MOD-GRID Pen Clip 9.84 (Autodesk Fusion 360 design; units mm, degrees)
part number: 2026-10-21-09-21-54-398
Autodesk Fusion 360 part; units mm, degrees
sketch "Clip A body" plane through (0, 0, 0) normal (1, 0, 0) x (0, 0, -1)
  line L0 (0, -11) -> (-11.0844, -11)
  line L1 (-11.0844, -11) -> (-11.0844, 11)
  line L2 (-11.0844, 11) -> (0, 11)
  line L3 (0, 11) -> (0, -11)
extrude "Extrude193" add sketch "Clip A body" along normal blind 7 and the other way blind 7 makes body 1
fillet "Fillet5" radius 2 4 edges at (0, 11, 0) (0, -11, 0) (0, -11, 11.0844) (0, 11, 11.0844) on bodies 1
sketch "Clip A bore" plane through (0, 0, 0) normal (1, 0, 0) x (0, 0, -1)
  circle A0 centre (-7.52, 0) radius 5.02
extrude "Extrude194" cut sketch "Clip A bore" along normal blind 14 and the other way blind 14 bodies 1
sketch "Clip A opening" plane through (0, 0, 0) normal (1, 0, 0) x (0, 0, -1)
  line L0 (-9.0844, -4.77) -> (-12.0844, -4.77)
  line L1 (-12.0844, -4.77) -> (-12.0844, 4.77)
  line L2 (-12.0844, 4.77) -> (-9.0844, 4.77)
  line L3 (-9.0844, 4.77) -> (-9.0844, -4.77)
extrude "Extrude195" cut sketch "Clip A opening" along normal blind 14 and the other way blind 14 bodies 1
sketch "Clip A relief" plane through (0, 0, 0) normal (1, 0, 0) x (0, 0, -1)
  arc A0 (-2.5561, 4.9639) -> (-14.1166, 2.401) centre (-7.52, 0) ccw
  arc A1 (-1.7076, 5.8124) -> (-15.2443, 2.8114) centre (-7.52, 0) ccw
  line L0 (-2.5561, 4.9639) -> (-1.7076, 5.8124)
  line L1 (-14.1166, 2.401) -> (-15.2443, 2.8114)
  circle A2 centre (-2.1318, 5.3882) radius 0.6
  circle A3 centre (-14.6805, 2.6062) radius 0.6
  arc A4 (-14.1166, -2.401) -> (-2.5561, -4.9639) centre (-7.52, 0) ccw
  arc A5 (-15.2443, -2.8114) -> (-1.7076, -5.8124) centre (-7.52, 0) ccw
  line L2 (-14.1166, -2.401) -> (-15.2443, -2.8114)
  line L3 (-2.5561, -4.9639) -> (-1.7076, -5.8124)
  circle A6 centre (-2.1318, -5.3882) radius 0.6
  circle A7 centre (-14.6805, -2.6062) radius 0.6
extrude "Extrude196" cut sketch "Clip A relief" along normal blind 14 and the other way blind 14 bodies 1
chamfer "Chamfer39" distance 0.5 angle 45 20 edges at (-7, 6.964, 6.635) (-7, 4.9639, 1.7076) (-7, 8.1037, 6.142) (-7, 8.2035, 11.0844) (-7, 10.4142, 10.4987) (-7, 11, 5.5422) (-7, 10.4142, 0.5858) (-7, 0, 0) (-7, -10.4142, 0.5858) (-7, -11, 5.5422) (-7, -10.4142, 10.4987) (-7, -8.2035, 11.0844) (-7, -8.1037, 6.142) (-7, -4.9639, 1.7076) (-7, -6.964, 6.635) (-7, -5.4089, 11.0844) (-7, -4.77, 10.0844) (-7, 0, 2.5) (-7, 4.77, 10.0844) (-7, 5.4089, 11.0844) tangent chain off on bodies 1
ref_plane "WorkPlane54" through (-7, 0, 0) normal (1, 0, 0) x (0, 1, 0)
sketch "Clip A legs" plane through (-7, 0, 0) normal (1, 0, 0) x (0, 0, -1)
  line L0 (-0.5, -5.45) -> (4.64, -5.45)
  line L1 (4.64, -5.45) -> (4.64, -5.93)
  line L2 (4.64, -5.93) -> (3.4, -7.19)
  line L3 (3.4, -7.19) -> (3.1, -6.32)
  line L4 (3.1, -6.32) -> (-0.5, -6.32)
  line L5 (-0.5, -6.32) -> (-0.5, -5.45)
  line L6 (-0.5, -2.55) -> (4.64, -2.55)
  line L7 (4.64, -2.55) -> (4.64, -2.07)
  line L8 (4.64, -2.07) -> (3.4, -0.81)
  line L9 (3.4, -0.81) -> (3.1, -1.68)
  line L10 (3.1, -1.68) -> (-0.5, -1.68)
  line L11 (-0.5, -1.68) -> (-0.5, -2.55)
  line L12 (-0.5, 2.55) -> (4.64, 2.55)
  line L13 (4.64, 2.55) -> (4.64, 2.07)
  line L14 (4.64, 2.07) -> (3.4, 0.81)
  line L15 (3.4, 0.81) -> (3.1, 1.68)
  line L16 (3.1, 1.68) -> (-0.5, 1.68)
  line L17 (-0.5, 1.68) -> (-0.5, 2.55)
  line L18 (-0.5, 5.45) -> (4.64, 5.45)
  line L19 (4.64, 5.45) -> (4.64, 5.93)
  line L20 (4.64, 5.93) -> (3.4, 7.19)
  line L21 (3.4, 7.19) -> (3.1, 6.32)
  line L22 (3.1, 6.32) -> (-0.5, 6.32)
  line L23 (-0.5, 6.32) -> (-0.5, 5.45)
extrude "Extrude197" add sketch "Clip A legs" along normal blind 4.76 bodies 1
ref_plane "WorkPlane55" through (-7, 0, 0) normal (1, 0, 0) x (0, 1, 0)
sketch "Clip A dimples" plane through (-7, 0, 0) normal (1, 0, 0) x (0, 0, -1)
  circle A0 centre (-8.5844, 8.5) radius 0.8
extrude "Extrude198" cut sketch "Clip A dimples" along normal blind 0.6 bodies 1
sketch "Clip B body" plane through (0, 0, 0) normal (1, 0, 0) x (0, 0, -1)
  line L0 (0, 19) -> (-11.0844, 19)
  line L1 (-11.0844, 19) -> (-11.0844, 41)
  line L2 (-11.0844, 41) -> (0, 41)
  line L3 (0, 41) -> (0, 19)
extrude "Extrude199" add sketch "Clip B body" along normal blind 7 and the other way blind 7 separate body makes body 2
fillet "Fillet6" radius 2 4 edges at (0, 41, 0) (0, 19, 0) (0, 19, 11.0844) (0, 41, 11.0844) on bodies 2
sketch "Clip B bore" plane through (0, 0, 0) normal (1, 0, 0) x (0, 0, -1)
  circle A0 centre (-7.52, 30) radius 5.02
extrude "Extrude200" cut sketch "Clip B bore" along normal blind 14 and the other way blind 14 bodies 2
sketch "Clip B opening" plane through (0, 0, 0) normal (1, 0, 0) x (0, 0, -1)
  line L0 (-9.0844, 25.23) -> (-12.0844, 25.23)
  line L1 (-12.0844, 25.23) -> (-12.0844, 34.77)
  line L2 (-12.0844, 34.77) -> (-9.0844, 34.77)
  line L3 (-9.0844, 34.77) -> (-9.0844, 25.23)
extrude "Extrude201" cut sketch "Clip B opening" along normal blind 14 and the other way blind 14 bodies 2
sketch "Clip B relief" plane through (0, 0, 0) normal (1, 0, 0) x (0, 0, -1)
  arc A0 (-2.5561, 34.9639) -> (-14.1166, 32.401) centre (-7.52, 30) ccw
  arc A1 (-1.7076, 35.8124) -> (-15.2443, 32.8114) centre (-7.52, 30) ccw
  line L0 (-2.5561, 34.9639) -> (-1.7076, 35.8124)
  line L1 (-14.1166, 32.401) -> (-15.2443, 32.8114)
  circle A2 centre (-2.1318, 35.3882) radius 0.6
  circle A3 centre (-14.6805, 32.6062) radius 0.6
  arc A4 (-14.1166, 27.599) -> (-2.5561, 25.0361) centre (-7.52, 30) ccw
  arc A5 (-15.2443, 27.1886) -> (-1.7076, 24.1876) centre (-7.52, 30) ccw
  line L2 (-14.1166, 27.599) -> (-15.2443, 27.1886)
  line L3 (-2.5561, 25.0361) -> (-1.7076, 24.1876)
  circle A6 centre (-2.1318, 24.6118) radius 0.6
  circle A7 centre (-14.6805, 27.3938) radius 0.6
extrude "Extrude202" cut sketch "Clip B relief" along normal blind 14 and the other way blind 14 bodies 2
chamfer "Chamfer40" distance 0.5 angle 45 20 edges at (-7, 36.964, 6.635) (-7, 34.9639, 1.7076) (-7, 38.1037, 6.142) (-7, 38.2035, 11.0844) (-7, 40.4142, 10.4987) (-7, 41, 5.5422) (-7, 40.4142, 0.5858) (-7, 30, 0) (-7, 19.5858, 0.5858) (-7, 19, 5.5422) (-7, 19.5858, 10.4987) (-7, 21.7965, 11.0844) (-7, 21.8963, 6.142) (-7, 25.0361, 1.7076) (-7, 23.036, 6.635) (-7, 24.5911, 11.0844) (-7, 25.23, 10.0844) (-7, 30, 2.5) (-7, 34.77, 10.0844) (-7, 35.4089, 11.0844) tangent chain off on bodies 2
ref_plane "WorkPlane56" through (-7, 0, 0) normal (1, 0, 0) x (0, 1, 0)
sketch "Clip B legs" plane through (-7, 0, 0) normal (1, 0, 0) x (0, 0, -1)
  line L0 (-0.5, 24.55) -> (4.64, 24.55)
  line L1 (4.64, 24.55) -> (4.64, 24.07)
  line L2 (4.64, 24.07) -> (3.4, 22.81)
  line L3 (3.4, 22.81) -> (3.1, 23.68)
  line L4 (3.1, 23.68) -> (-0.5, 23.68)
  line L5 (-0.5, 23.68) -> (-0.5, 24.55)
  line L6 (-0.5, 27.45) -> (4.64, 27.45)
  line L7 (4.64, 27.45) -> (4.64, 27.93)
  line L8 (4.64, 27.93) -> (3.4, 29.19)
  line L9 (3.4, 29.19) -> (3.1, 28.32)
  line L10 (3.1, 28.32) -> (-0.5, 28.32)
  line L11 (-0.5, 28.32) -> (-0.5, 27.45)
  line L12 (-0.5, 32.55) -> (4.64, 32.55)
  line L13 (4.64, 32.55) -> (4.64, 32.07)
  line L14 (4.64, 32.07) -> (3.4, 30.81)
  line L15 (3.4, 30.81) -> (3.1, 31.68)
  line L16 (3.1, 31.68) -> (-0.5, 31.68)
  line L17 (-0.5, 31.68) -> (-0.5, 32.55)
  line L18 (-0.5, 35.45) -> (4.64, 35.45)
  line L19 (4.64, 35.45) -> (4.64, 35.93)
  line L20 (4.64, 35.93) -> (3.4, 37.19)
  line L21 (3.4, 37.19) -> (3.1, 36.32)
  line L22 (3.1, 36.32) -> (-0.5, 36.32)
  line L23 (-0.5, 36.32) -> (-0.5, 35.45)
extrude "Extrude203" add sketch "Clip B legs" along normal blind 4.76 bodies 2
ref_plane "WorkPlane57" through (-7, 0, 0) normal (1, 0, 0) x (0, 1, 0)
sketch "Clip B dimples" plane through (-7, 0, 0) normal (1, 0, 0) x (0, 0, -1)
  circle A0 centre (-8.5844, 38.5) radius 0.8
  circle A1 centre (-5.5844, 38.5) radius 0.8
extrude "Extrude204" cut sketch "Clip B dimples" along normal blind 0.6 bodies 2
equation "pen_d = 9.84 mm" comment "Pen diameter (measured by user)"
equation "pen_clear = 0.2 mm" comment "Diametral clearance in the bore"
equation "bore_d = pen_d + pen_clear" comment "Clip bore diameter"
equation "lip_wrap = 20 deg" comment "Lip wrap past the bore equator; sets snap force AND max print overhang"
equation "clip_len = 14 mm" comment "Clip length along the pen axis"
equation "body_hw = 11 mm" comment "Body half width; must cover the pegs"
equation "top_wall = 2 mm" comment "Wall over the bore (the bed face when printed)"
equation "grid_pitch = 8 mm" comment "MOD-GRID pitch"
equation "peg_pitch_y = 2 * grid_pitch" comment "Peg spacing across the pen (2 grid cells)"
equation "peg_w_a = 5.30 mm" comment "Clip A peg width (interference direction)"
equation "peg_w_b = 5.15 mm" comment "Clip B peg width"
equation "peg_x = 4.90 mm" comment "Peg size along the pen axis - UNDER 5.00 so it slides"
equation "peg_h = 5.0 mm" comment "Peg depth; under the 3.0 mm plate so it sits flush"
equation "peg_slot_w = 1.0 mm" comment "Relief slot that lets the peg compress"
equation "relief_y0 = 5.6 mm" comment "Inner edge of the lip relief slot"
equation "relief_w = 1.2 mm" comment "Lip relief slot width"
equation "relief_z0 = 3.0 mm" comment "Relief slot start height (leaves material over the peg)"
equation "relief_z1 = 5.0 mm" comment "Relief slot top"
equation "first_layer_cham = 0.5 mm" comment "Elephant-foot chamfer on the bed face"
equation "peg_cham = 0.3 mm" comment "Lead-in chamfer on the peg tips"
equation "id_dimple_d = 1.6 mm" comment "Identification dimple diameter"
equation "id_dimple_h = 0.6 mm" comment "Identification dimple depth"
equation "bore_cz = bottom_wall + bore_d / 2" comment "Bore centre height (bore tangent to the plate)"
equation "body_h = lip_z + land_h" comment "Overall body height"
equation "lip_gap = pen_d - lip_spread" comment "Opening between the lips"
equation "lip_z = bore_cz + sqrt(( bore_d / 2 ) ^ 2 - ( lip_gap / 2 ) ^ 2)" comment "Lip tip height"
equation "bottom_wall = 2.5 mm" comment "Material under the teardrop apex"
equation "land_h = 2 mm" comment "Slot depth above the lips = height of the bed lands"
equation "peg_root_a = 5.26 mm" comment "Clip A split-axis width at the root (official nominal)"
equation "peg_tip_a = 5.02 mm" comment "Clip A split-axis width at the tip (lead-in taper)"
equation "peg_solid_a = 5.13 mm" comment "Clip A solid-axis width (no slot, crush fit)"
equation "peg_root_b = 5.14 mm" comment "Clip B split-axis root - one step looser"
equation "peg_tip_b = 4.94 mm" comment "Clip B split-axis tip"
equation "peg_solid_b = 5.05 mm" comment "Clip B solid-axis width"
equation "lip_spread = 0.30 mm" comment "How far the pen must spread the lips - sets snap force AND lip stress"
equation "sup_gap = 0.2 mm" comment "Z-gap under the peg: exactly one layer, so it releases"
equation "sup_inset = 0.3 mm" comment "Support block inset from the peg footprint"
equation "sup_neck_h = 0.6 mm" comment "Height of the break-off ridges on top of the support block"
equation "sup_ridge_w = 0.6 mm" comment "Width of each break-off ridge - keep small so it snaps"
equation "sup_overlap = 0.05 mm" comment "Ridge overlap INTO the peg so nothing floats"
equation "lip_t = 2.0 mm" comment "CONSTANT lip thickness - 5 perimeters at 0.4 nozzle"
equation "relief_a0 = -45 deg" comment "Relief slot start angle from the bore equator; lower = longer, softer lip"
equation "socket_size = 5.00 mm" comment "Connector socket - identical to a baseplate hole"
equation "socket_depth = 2.5 mm" comment "Socket depth (connector is 5.0 tall, 3.0 of it in the plate)"
equation "socket_gable = 45 deg" comment "Gable roof so the socket needs no support when printed on end"
equation "socket_web_w = 2.0 mm" comment "Channel joining the sockets, to clear the connector web"
equation "con_post_solid = 5.13 mm" comment "Connector post, solid axis"
equation "con_post_root = 5.26 mm" comment "Connector post, split axis at the root"
equation "con_post_tip = 5.02 mm" comment "Connector post, split axis at the tip"
equation "con_slot_w = 1.0 mm" comment "Connector split slot"
equation "con_h = 5.0 mm" comment "Connector height"
equation "con_web_t = 1.8 mm" comment "Web joining the two posts"
equation "con_web_z = 3.0 mm" comment "Web starts here, so it sits above the plate"
equation "leg_hole_len = 4.90 mm - leg_clear" comment "Leg extent along the pen axis; 0.10 clearance in the 5.00 hole"
equation "leg_inner_hw = 1.45 mm" comment "Leg inner face from pair centre -> 2.90 gap, a long soft cantilever"
equation "leg_shank_hw = 2.39 mm - leg_clear / 2" comment "Relaxed shank half-span -> 4.78 pair, slides into the hole"
equation "barb_hw = 3.19 mm" comment "Barb peak half-span -> 6.38 pair, squeezes 1.38 to pass"
equation "barb_z = -3.40 mm" comment "Barb peak depth below the seating face"
equation "catch_z = -3.10 mm" comment "Catch face: 0.10 below the 3.00 plate"
equation "leg_tip_z = -4.64 mm" comment "Leg tip"
equation "leg_tip_hw = 2.00 mm - leg_clear / 2" comment "Tip half-span, sets the ~45 deg lead-in ramp"
equation "body_corner_r = 2.0 mm" comment "Rounded outer corners - a bare rectangle looks unfinished"
equation "leg_clear = 0.14 mm" comment "Shrinks the leg LENGTH and SHANK (not the barb). 0 = official nominal (4.90 long, 4.78 shank) which assumes the hole prints a true 5.00; FDM holes usually come out undersize, so raise this if the legs crush going in. MEASURED: the printed hole came out 0.14 under nominal, i.e. 0.07 per wall. External features run over by the same bias, so a 4.90 leg prints ~5.04; 0.14 here brings the PRINTED leg back to 4.90 in a true 5.00 hole. Zero it if the printer is dimensionally calibrated."
equation "d830 = clip_len / 2"
equation "d832 = clip_len / 2"
equation "d835 = body_corner_r"
equation "d836 = clip_len"
equation "d838 = clip_len"
equation "d840 = clip_len"
equation "d842 = clip_len"
equation "d844 = clip_len"
equation "d846 = clip_len"
equation "d848 = first_layer_cham"
equation "d849 = -clip_len / 2"
equation "d851 = leg_hole_len"
equation "d853 = -clip_len / 2"
equation "d855 = id_dimple_h"
equation "d857 = clip_len / 2"
equation "d859 = clip_len / 2"
equation "d862 = body_corner_r"
equation "d863 = clip_len"
equation "d865 = clip_len"
equation "d867 = clip_len"
equation "d869 = clip_len"
equation "d871 = clip_len"
equation "d873 = clip_len"
equation "d875 = first_layer_cham"
equation "d876 = -clip_len / 2"
equation "d878 = leg_hole_len"
equation "d880 = -clip_len / 2"
equation "d882 = id_dimple_h"
named bodies: "Clip A", "Clip B"
